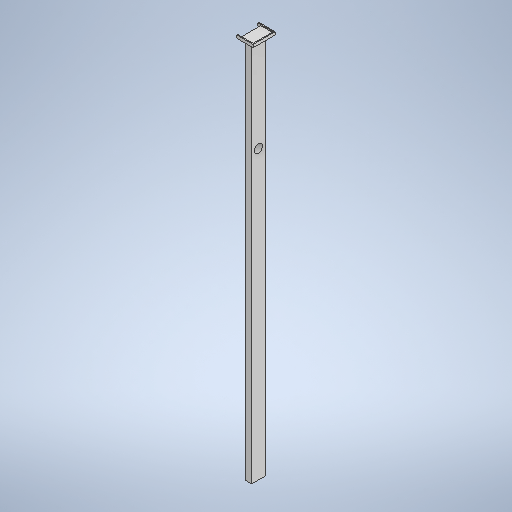
# Autodesk Inventor part: iterasi3-cetak
Saved by Autodesk Inventor 2026.2 (Build 302298010, 298A)
## iProperties
Created: 2026-11-17
Part Number: iterasi3-cetak
Material: Generic
Document SubType Name: Modeling
Designer: Acer
Density: 1 g/cm^3
Appearance: Default
Author: Acer
Autodesk Inventor part; units mm, degrees
ref_plane "YZ Plane" through (0, 0, 0) normal (1, 0, 0) x (0, 1, 0)
ref_plane "XZ Plane" through (0, 0, 0) normal (0, 1, 0) x (-1, 0, 0)
ref_plane "XY Plane" through (0, 0, 0) normal (0, 0, 1) x (1, 0, 0)
sketch "Sketch1" plane through (0, 0, 0) normal (1, 0, 0) x (0, 1, 0)
  line L0 (200, 7) -> (-200, 7)
  line L1 (-200, 7) -> (-200, -7)
  line L2 (-200, -7) -> (200, -7)
  line L3 (200, -7) -> (200, 7)
  circle A0 centre (100, 0) radius 4.3
  point P0 (0, 0)
  dimension "d2" = 14
  dimension "d4" = 8.6
  constraints: 8 end point, 2 parallel, 1 centre point, 1 horizontal, 1 perpendicular
  measures "d2" distance of L1.end L0.end
  measures "d4" diameter of A0
extrude "Extrusion1" add sketch "Sketch1" along normal blind 6
sketch "Sketch2" plane through (0, 200, 7) normal (0, 1, 0) x (1, 0, 0)
  line L0 (0, 14) -> (0, 0) projected
  line L1 (0, 0) -> (6, 0) projected
  line L2 (6, 14) -> (6, 0) projected
  line L3 (0, 14) -> (6, 14) projected
  line L4 (11, 17.5) -> (-5, 17.5)
  line L5 (-5, 17.5) -> (-5, -3.5)
  line L6 (-5, -3.5) -> (11, -3.5)
  line L7 (11, -3.5) -> (11, 17.5)
  line L8 (11, 17.5) -> (-5, -3.5) construction
  line L9 (-5, 17.5) -> (11, -3.5) construction
  point P0 (0, 7)
  point P1 (3, 7)
  dimension "d7" = 16
  dimension "d8" = 21
  constraints: 12 end point, 2 midpoint, 2 parallel, 1 horizontal, 1 perpendicular
  measures "d7" distance of L6.end L5.end
  measures "d8" distance of L5.end L4.end
extrude "Extrusion2" add sketch "Sketch2" along normal blind 2 contours L3 L2 L1 L0 | L7 L6 L5 L4
sketch "Sketch5" plane through (0, 202, 7) normal (0, 1, 0) x (1, 0, 0)
  line L0 (6, 11.3) -> (0, 11.3) projected
  line L1 (11, -3.5) -> (11, 17.5) projected
  line L2 (11, 17.5) -> (-5, 17.5) projected
  line L3 (11, 17.5) -> (12, 17.5)
  line L4 (12, 17.5) -> (12, -3.5)
  line L5 (12, -3.5) -> (11, -3.5)
  line L6 (11, -3.5) -> (11, 17.5)
  line L7 (-5, 17.5) -> (-5, -3.5) projected
  line L8 (-5, -3.5) -> (11, -3.5) projected
  line L9 (11, 17.5) -> (-5, 17.5) projected
  point P0 (0, 7)
  dimension "d19" = 1
  dimension "d20" = 21
  constraints: 8 end point, 2 parallel, 1 horizontal, 1 perpendicular
  measures "d19" distance of L4.end L5.end
  measures "d20" distance of L3.end L4.end
extrude "Extrusion5" add sketch "Sketch5" along normal mid plane 2 contours L1 L3 L4 L5
sketch "Sketch6" plane through (11, 200, 10.5) normal (1, 0, 0) x (0, 0, -1)
  line L0 (21, 1) -> (0, 1) projected
  line L1 (0, 0) -> (0, 1) projected
  line L2 (21, 1) -> (0, 1)
  line L3 (0, 1) -> (0, 0)
  line L4 (0, 0) -> (21, 0)
  line L5 (21, 0) -> (21, 1)
  point P0 (10.5, -200)
  constraints: 8 end point, 2 parallel, 1 horizontal, 1 perpendicular
extrude "Extrusion6" add sketch "Sketch6" along normal blind 1
sketch "Sketch11" plane through (-5, 200, 10.5) normal (0, 0, 1) x (1, 0, 0)
  line L0 (0, 0) -> (2, 0) projected
  line L1 (17, 3) -> (0, 3)
  line L2 (0, 3) -> (0, 0)
  line L3 (0, 0) -> (17, 0)
  line L4 (17, 0) -> (17, 3)
  point P0 (5, -200)
  constraints: 8 end point, 2 parallel, 1 horizontal, 1 perpendicular
extrude "Extrusion7" add sketch "Sketch11" along normal blind 1
sketch "Sketch12" plane through (-5, 200, -10.5) normal (0, 0, -1) x (-1, 0, 0)
  line L0 (-2, 0) -> (0, 0) projected
  line L1 (-17, 0) -> (-17, 3) projected
  line L2 (0, 0) -> (-17, 0)
  line L3 (-17, 0) -> (-17, 3)
  line L4 (-17, 3) -> (0, 3)
  line L5 (0, 3) -> (0, 0)
  point P0 (-5, -200)
  constraints: 8 end point, 2 parallel, 1 horizontal, 1 perpendicular
extrude "Extrusion8" add sketch "Sketch12" along normal blind 1
sketch "Sketch14" plane through (0, 202, 7) normal (0, 1, 0) x (1, 0, 0)
  line L0 (-5, 17.5) -> (-5, -3.5) projected
  line L1 (-5, -3.5) -> (11, -3.5) projected
  line L2 (-5, 17.5) -> (-2, 17.5)
  line L3 (-2, 17.5) -> (-2, -3.5)
  line L4 (-2, -3.5) -> (-5, -3.5)
  line L5 (-5, -3.5) -> (-5, 17.5)
  point P0 (0, 7)
  dimension "d41" = 3
  constraints: 8 end point, 2 parallel, 1 horizontal, 1 perpendicular, 1 point on line
  measures "d41" distance of L3.end L4.end
extrude "Extrusion10" cut sketch "Sketch14" against normal blind 10
body "Solid1"
